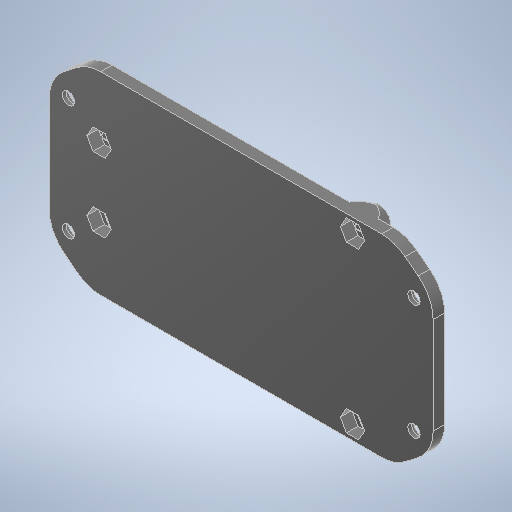
# Autodesk Inventor part: 3D_DC_fix
Saved by Autodesk Inventor 2025.3 (Build 293356030, 356C)
## iProperties
Created: 2025-08-01
Part Number: 3D_DC_fix
Material: 一般
Document SubType Name: Modeling
Designer: ibuki_ono
Density: 1 g/cm^3
Appearance: 滑らか - 黒
Author: ibuki_ono
## iProperties of the stored document 3D_DC_fix_3D プリント.ipt
Created: 2025-08-01
Part Number: 3D_DC_fix_3D プリント
Material: 一般
Document SubType Name: Modeling
Designer: ibuki_ono
Density: 1 g/cm^3
Appearance: 既定
Author: ibuki_ono
Autodesk Inventor part; units mm, degrees
ref_plane "YZ Plane" through (0, 0, 0) normal (1, 0, 0) x (0, 1, 0)
ref_plane "XZ Plane" through (0, 0, 0) normal (0, 1, 0) x (-1, 0, 0)
ref_plane "XY Plane" through (0, 0, 0) normal (0, 0, 1) x (1, 0, 0)
ref_plane "作業平面1" through (0, 0, 4) normal (0, 0, 1) x (1, 0, 0)
sketch "スケッチ1" plane through (0, 0, 4) normal (0, 0, 1) x (1, 0, 0)
  line L0 (40, 25.2) -> (-40, 25.2) projected
  line L1 (-40, -25.2) -> (40, -25.2) projected
  line L2 (40, -25.2) -> (40, 25.2) projected
  line L3 (-40, 25.2) -> (-40, -25.2) projected
  line L4 (-40, 17.5) -> (-50, 17.5)
  line L5 (-50, 17.5) -> (-50, -17.5)
  line L6 (-50, -17.5) -> (-40, -17.5)
  line L7 (-40, -17.5) -> (-40, 17.5)
  line L8 (40, 17.5) -> (50, 17.5)
  line L9 (50, 17.5) -> (50, -17.5)
  line L10 (50, -17.5) -> (40, -17.5)
  line L11 (40, -17.5) -> (40, 17.5)
  line L12 (-40, 25.2) -> (-50, 17.5)
  line L13 (-50, -17.5) -> (-40, -25.2)
  line L14 (40, 25.2) -> (50, 17.5)
  line L15 (50, -17.5) -> (40, -25.2)
  point P0 (0, 0)
  point P1 (-40, 0)
  point P2 (40, 0)
  dimension "d0" = 10
  dimension "d1" = 35
  dimension "d2" = 10
  dimension "d3" = 35
  constraints: 24 end point, 5 parallel, 4 midpoint, 3 point on line, 2 horizontal, 2 perpendicular
  measures "d0" distance of L6.end L5.end
  measures "d1" distance of L5.end L4.end
  measures "d2" distance of L9.end L10.end
  measures "d3" distance of L8.end L9.end
extrude "押し出し1" add sketch "スケッチ1" along normal blind 3
sketch "スケッチ2" plane through (0, 0, 4) normal (0, 0, -1) x (-1, 0, 0)
  line L0 (45, 15) -> (-45, 15) construction
  line L1 (-45, 15) -> (-45, -15) construction
  line L2 (-45, -15) -> (45, -15) construction
  line L3 (45, -15) -> (45, 15) construction
  line L4 (45, 15) -> (-45, -15) construction
  line L5 (-45, 15) -> (45, -15) construction
  point P0 (0, 0)
  dimension "d6" = 90
  dimension "d7" = 30
  constraints: 12 end point, 2 midpoint, 2 parallel, 1 horizontal, 1 perpendicular
  measures "d6" distance of L2.end L1.end
  measures "d7" distance of L1.end L0.end
hole "穴1" at (-45, -15, 4) at (-45, 15, 4) at (45, -15, 4) at (45, 15, 4) direction (0, 0, 1) diameter 3.2 end through all counterbore diameter 7 counterbore depth 2
sketch "スケッチ3" plane through (0, 0, 4) normal (0, 0, -1) x (-1, 0, 0)
  circle A0 centre (37, -9) radius 1.6 projected
  circle A1 centre (37, 9) radius 1.6 projected
  circle A2 centre (-29, -21.5) radius 1.6 projected
  circle A3 centre (-29, 21.5) radius 1.6 projected
  circle A4 centre (37, -9) radius 3
  circle A5 centre (37, 9) radius 3
  circle A6 centre (-29, -21.5) radius 3
  circle A7 centre (-29, 21.5) radius 3
  point P0 (0, 0)
  dimension "d15" = 6
  dimension "d16" = 6
  dimension "d17" = 6
  dimension "d18" = 6
  constraints: 4 centre point, 4 coincident
  measures "d15" diameter of A4
  measures "d16" diameter of A5
  measures "d17" diameter of A6
  measures "d18" diameter of A7
extrude "押し出し2" add sketch "スケッチ3" along normal blind 4 contours A0 | A1 | A2 | A3 | A4 | A5 | A6 | A7
sketch "スケッチ4" plane through (-37, -9, 0) normal (0, 0, -1) x (-1, 0, 0)
  circle A0 centre (0, 0) radius 3 projected
  circle A1 centre (0, 18) radius 3 projected
  circle A2 centre (-66, -12.5) radius 3 projected
  circle A3 centre (-66, 30.5) radius 3 projected
  point P0 (-37, 9)
hole "穴2" at (-37, -9, 0) at (-37, 9, 0) at (29, 21.5, 0) at (29, -21.5, 0) direction (0, 0, 1) diameter 3.2 end through all
chamfer "面取り2" distance 4 angle 30 1 edges at (-34, -9, 4) measured on face at (-34, -9, 3.5)
chamfer "面取り3" distance 4 angle 30 1 edges at (-34, 9, 4) measured on face at (-34, 9, 3.5)
chamfer "面取り4" distance 4 angle 30 1 edges at (32, -21.5, 4) measured on face at (32, -21.5, 3.5)
chamfer "面取り5" distance 4 angle 30 1 edges at (32, 21.5, 4) measured on face at (32, 21.5, 3.5)
sketch "スケッチ5" plane through (0, 0, 7) normal (0, 0, 1) x (1, 0, 0)
  circle A0 centre (-37, 9) radius 1.6 projected
  circle A1 centre (29, 21.5) radius 1.6 projected
  line L0 (-33.8246, 9) -> (-35.4123, 6.25)
  line L1 (-35.4123, 6.25) -> (-38.5877, 6.25)
  line L2 (-38.5877, 6.25) -> (-40.1754, 9)
  line L3 (-40.1754, 9) -> (-38.5877, 11.75)
  line L4 (-38.5877, 11.75) -> (-35.4123, 11.75)
  line L5 (-35.4123, 11.75) -> (-33.8246, 9)
  circle A2 centre (29, 21.5) radius 3 projected
  line L6 (32.1754, 21.5) -> (30.5877, 18.75)
  line L7 (30.5877, 18.75) -> (27.4123, 18.75)
  line L8 (27.4123, 18.75) -> (25.8246, 21.5)
  line L9 (25.8246, 21.5) -> (27.4123, 24.25)
  line L10 (27.4123, 24.25) -> (30.5877, 24.25)
  line L11 (30.5877, 24.25) -> (32.1754, 21.5)
  point P0 (0, 0)
  dimension "d43" = 5.5
  dimension "d44" = 5.5
  constraints: 24 end point, 2 coincident, 2 horizontal alignment, 26 other
  measures "d43" distance between parallel lines of L1 L4
  measures "d44" distance between parallel lines of L7 L10
extrude "押し出し3" cut sketch "スケッチ5" against normal blind 3 contours A0 | A1 | L0 L1 L2 L3 L4 L5 | A2 L6 L7 L8 L9 L10 L11 | A2 L11 L6 | A2 L10 L11 | L6 L7 A2 | A2 L9 L10 | L7 L8 A2 | A2 L8 L9
sketch "スケッチ6" plane through (0, 0, 4) normal (0, 0, 1) x (1, 0, 0)
  circle A0 centre (-37, 9) radius 1.6 projected
  line L0 (-38.5877, 11.75) -> (-35.4123, 11.75) projected
  line L1 (-40.1754, 9) -> (-38.5877, 11.75) projected
  line L2 (-38.5877, 6.25) -> (-40.1754, 9) projected
  line L3 (-35.4123, 6.25) -> (-38.5877, 6.25) projected
  line L4 (-33.8246, 9) -> (-35.4123, 6.25) projected
  line L5 (-35.4123, 11.75) -> (-33.8246, 9) projected
  circle A1 centre (29, 21.5) radius 1.6 projected
  line L6 (27.4123, 24.25) -> (30.5877, 24.25) projected
  line L7 (25.8246, 21.5) -> (27.4123, 24.25) projected
  line L8 (27.4123, 18.75) -> (25.8246, 21.5) projected
  line L9 (30.5877, 18.75) -> (27.4123, 18.75) projected
  line L10 (32.1754, 21.5) -> (30.5877, 18.75) projected
  line L11 (30.5877, 24.25) -> (32.1754, 21.5) projected
  line L12 (-39.2517, 7.4) -> (-34.7483, 7.4)
  line L13 (-34.4885, 7.85) -> (-36.7402, 11.75)
  line L14 (-37.2598, 11.75) -> (-39.5115, 7.85)
  line L15 (28.7402, 24.25) -> (26.4885, 20.35)
  circle A2 centre (29, 21.5) radius 3 projected
  line L16 (26.7483, 19.9) -> (31.2517, 19.9)
  line L17 (31.5115, 20.35) -> (29.2598, 24.25)
  line L18 (25.8246, 21.5) -> (27.4123, 24.25) projected
  line L19 (30.5877, 24.25) -> (32.1754, 21.5) projected
  line L20 (30.5877, 18.75) -> (27.4123, 18.75) projected
  circle A3 centre (29, 21.5) radius 1.6 projected
  circle A4 centre (-37, 9) radius 1.6 projected
  line L21 (-40.1754, 9) -> (-38.5877, 11.75) projected
  line L22 (-35.4123, 11.75) -> (-33.8246, 9) projected
  line L23 (-35.4123, 6.25) -> (-38.5877, 6.25) projected
  point P0 (0, 0)
  point P1 (30.3856, 22.3)
  point P2 (27.6144, 22.3)
  point P3 (29, 19.9)
  point P4 (-38.3856, 9.8)
  point P5 (-37, 7.4)
  point P6 (-35.6144, 9.8)
  constraints: 12 end point, 12 point on line, 7 parallel, 6 tangent, 1 horizontal
extrude "押し出し4" cut sketch "スケッチ6" against normal blind 0.2 contours A0 L13 L4 L12 | A0 L14 L0 L13 | L12 L2 L14 A0 | A1 L17 L10 L16 | A1 L15 L6 L17 | L16 L8 L15 A1
mirror "ミラー1" about plane through (0, 0, 0) normal (0, 1, 0) of "押し出し3", "押し出し4"
sketch "スケッチ7" plane through (0, 0, 4) normal (0, 0, -1) x (-1, 0, 0)
  line L0 (30, 14.5) -> (-38, 14.5)
  line L1 (-38, 14.5) -> (-38, -14.5)
  line L2 (-38, -14.5) -> (30, -14.5)
  line L3 (30, -14.5) -> (30, 14.5)
  line L4 (30, 14.5) -> (-38, -14.5) construction
  line L5 (-38, 14.5) -> (30, -14.5) construction
  line L6 (30, 22.2) -> (-22, 22.2)
  line L7 (-22, 22.2) -> (-22, -22.2)
  line L8 (-22, -22.2) -> (30, -22.2)
  line L9 (30, -22.2) -> (30, 22.2)
  line L10 (30, 22.2) -> (-22, -22.2) construction
  line L11 (-22, 22.2) -> (30, -22.2) construction
  circle A0 centre (37, -9) radius 1.6 projected
  line L12 (40, -25.2) -> (-25.1921, -25.2) projected
  circle A1 centre (-29, -21.5) radius 1.6 projected
  circle A2 centre (-45, -15) radius 1.6 projected
  point P0 (0, 0)
  point P1 (-4, 0)
  point P2 (4, 0)
  point P3 (-22, 14.5)
  point P4 (-22, -14.5)
  dimension "d49" = 7
  dimension "d50" = 3
  dimension "d51" = 7
  dimension "d52" = 7
  dimension "d53" = 7
  constraints: 24 end point, 4 midpoint, 4 parallel, 2 horizontal, 2 horizontal alignment, 2 perpendicular, 1 collinear
  measures "d49" distance from line of A0.centre L9
  measures "d50" distance between parallel lines of L12 L8
  measures "d51" distance from line of L7 A1.centre
  measures "d52" distance from line of A1.centre L2
  measures "d53" distance from line of A2.centre L1
extrude "押し出し5" cut sketch "スケッチ7" against normal blind 2 contours L3 L2 L7 L0 | L0 L7 L6 L9 | L7 L2 L1 L0 | L9 L8 L7 L2
fillet "フィレット1" radius 5 8 edges at (-30, -22.2, 5) (-30, 22.2, 5) (22, 22.2, 5) (22, 14.5, 5) (38, 14.5, 5) (38, -14.5, 5) (22, -14.5, 5) (22, -22.2, 5)
chamfer "面取り6" distance 2 angle 45 14 edges at (-3.866, -22.2, 6) (20.3705, -21.1211, 6) (23.8976, -15.5789, 6) (30, -14.5, 6) (36.5355, -13.0355, 6) (38, 0, 6) (36.5355, 13.0355, 6) (29.866, 14.5, 6) (23.6295, 15.5789, 6) (20.1024, 21.1211, 6) (-4, 22.2, 6) (-28.5355, 20.7355, 6) (-30, 0, 6) (-28.5355, -20.7355, 6)
fillet "フィレット2" radius 10 8 edges at (-50, 17.5, 5.5) (-40, 25.2, 5.5) (-50, -17.5, 5.5) (-40, -25.2, 5.5) (40, 25.2, 5.5) (50, 17.5, 5.5) (50, -17.5, 5.5) (40, -25.2, 5.5)
equation "\"d44\" = d43"
equation "\"d51\" = d49"
equation "\"d52\" = d49"
equation "\"d53\" = d49"
